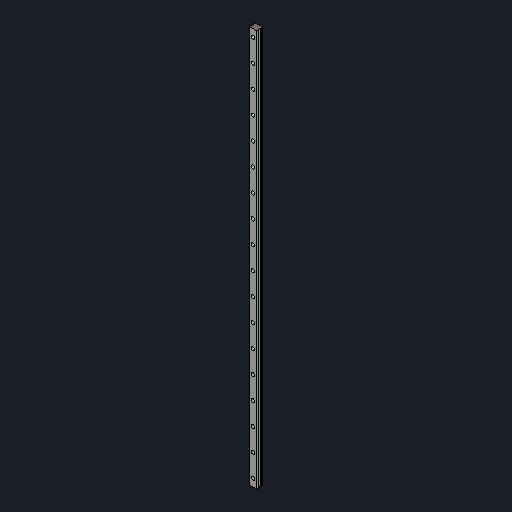
# Autodesk Inventor part: SBI20+1060N
Saved by Autodesk Inventor 2027.1 (Build 311270010, 270A)
## iProperties
Created: 2026-11-14
Part Number: SBI20+1060N
Material: Stainless Steel
Description: SBC catalogue mounting envelope; raceway section simplified
Document SubType Name: Modeling
Designer: queezz
Density: 8 g/cm^3
Appearance: Semi-Polished
Author: queezz
Autodesk Inventor part; units mm, degrees
ref_plane "Rail footprint plane" through (0, 0, 0) normal (0, 0, 1) x (1, 0, 0)
sketch "Rail footprint" plane through (0, 0, 0) normal (0, 0, 1) x (1, 0, 0)
  line L0 (-10, 0) -> (10, 0)
  line L1 (10, 0) -> (10, 1060)
  line L2 (10, 1060) -> (-10, 1060)
  line L3 (-10, 1060) -> (-10, 0)
  constraints: 8 end point, 2 parallel, 1 horizontal, 1 perpendicular
extrude "Rail envelope" add sketch "Rail footprint" along normal blind 16.5
ref_plane "Rail through holes layout plane" through (0, 0, 16.5) normal (0, 0, 1) x (1, 0, 0)
sketch "Rail through holes layout" plane through (0, 0, 16.5) normal (0, 0, 1) x (1, 0, 0)
  circle A0 centre (0, 20) radius 3
  circle A1 centre (0, 80) radius 3
  circle A2 centre (0, 140) radius 3
  circle A3 centre (0, 200) radius 3
  circle A4 centre (0, 260) radius 3
  circle A5 centre (0, 320) radius 3
  circle A6 centre (0, 380) radius 3
  circle A7 centre (0, 440) radius 3
  circle A8 centre (0, 500) radius 3
  circle A9 centre (0, 560) radius 3
  circle A10 centre (0, 620) radius 3
  circle A11 centre (0, 680) radius 3
  circle A12 centre (0, 740) radius 3
  circle A13 centre (0, 800) radius 3
  circle A14 centre (0, 860) radius 3
  circle A15 centre (0, 920) radius 3
  circle A16 centre (0, 980) radius 3
  circle A17 centre (0, 1040) radius 3
  constraints: 18 centre point
extrude "Rail through holes" cut sketch "Rail through holes layout" against normal blind 16.5
ref_plane "Rail head recesses layout plane" through (0, 0, 16.5) normal (0, 0, 1) x (1, 0, 0)
sketch "Rail head recesses layout" plane through (0, 0, 16.5) normal (0, 0, 1) x (1, 0, 0)
  circle A0 centre (0, 20) radius 4.75
  circle A1 centre (0, 80) radius 4.75
  circle A2 centre (0, 140) radius 4.75
  circle A3 centre (0, 200) radius 4.75
  circle A4 centre (0, 260) radius 4.75
  circle A5 centre (0, 320) radius 4.75
  circle A6 centre (0, 380) radius 4.75
  circle A7 centre (0, 440) radius 4.75
  circle A8 centre (0, 500) radius 4.75
  circle A9 centre (0, 560) radius 4.75
  circle A10 centre (0, 620) radius 4.75
  circle A11 centre (0, 680) radius 4.75
  circle A12 centre (0, 740) radius 4.75
  circle A13 centre (0, 800) radius 4.75
  circle A14 centre (0, 860) radius 4.75
  circle A15 centre (0, 920) radius 4.75
  circle A16 centre (0, 980) radius 4.75
  circle A17 centre (0, 1040) radius 4.75
  constraints: 18 centre point
extrude "Rail head recesses" cut sketch "Rail head recesses layout" against normal blind 8.5
sketch "Sketch4" plane through (0, 0, 0) normal (0, 1, 0) x (-1, 0, 0)
  line L0 (11, 4) -> (10, 4)
  line L1 (10, 4) -> (8.75, 6)
  line L2 (8.75, 6) -> (8.75, 10.4)
  line L3 (8.75, 10.4) -> (10, 12.4)
  line L4 (10, 12.4) -> (11, 12.4)
  line L5 (11, 12.4) -> (11, 4)
  line L6 (-11, 4) -> (-10, 4)
  line L7 (-10, 4) -> (-8.75, 6)
  line L8 (-8.75, 6) -> (-8.75, 10.4)
  line L9 (-8.75, 10.4) -> (-10, 12.4)
  line L10 (-10, 12.4) -> (-11, 12.4)
  line L11 (-11, 12.4) -> (-11, 4)
  constraints: 24 end point
extrude "Approximate symmetric side raceway profile" cut sketch "Sketch4" along normal blind 1060
body "Solid1"
